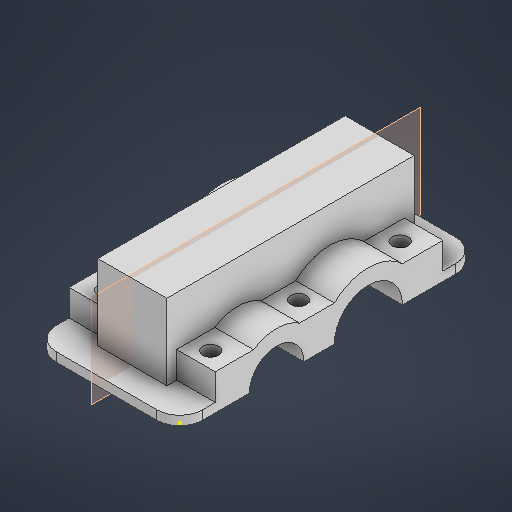
# Autodesk Inventor part: 箱盖
Saved by Autodesk Inventor 2026 (Build 300175000, 175)
## iProperties
Created: 2026-08-27
Part Number: 箱盖
Material: 常规
Document SubType Name: Modeling
Designer: 14170
Density: 1 g/cm^3
Appearance: 默认
Author: 14170
Autodesk Inventor part; units mm, degrees
ref_plane "YZ Plane" through (0, 0, 0) normal (1, 0, 0) x (0, 1, 0)
ref_plane "XZ Plane" through (0, 0, 0) normal (0, 1, 0) x (-1, 0, 0)
ref_plane "XY Plane" through (0, 0, 0) normal (0, 0, 1) x (1, 0, 0)
sketch "草图1" plane through (0, 0, 0) normal (0, 1, 0) x (-1, 0, 0)
  line L0 (0, -30) -> (0, -364.6)
  line L1 (30, -394.6) -> (163, -394.6)
  line L2 (193, -364.6) -> (193, -30)
  line L3 (163, 0) -> (30, 0)
  arc A0 (163, -394.6) -> (193, -364.6) centre (163, -364.6) ccw
  arc A1 (0, -364.6) -> (30, -394.6) centre (30, -364.6) ccw
  arc A2 (30, 0) -> (0, -30) centre (30, -30) ccw
  arc A3 (193, -30) -> (163, 0) centre (163, -30) ccw
  point P0 (0, 0)
  point P1 (0, -394.6)
  point P2 (193, -394.6)
  point P3 (193, 0)
  dimension "d0" = 394.6
  dimension "d1" = 193
  dimension "d46" = 30
  constraints: 8 end point, 8 point on circle, 8 point on line, 8 tangent, 4 centre point, 3 equal radius, 3 perpendicular, 1 vertical
  measures "d0" distance of point (0, 0) point (0, -394.6)
  measures "d1" distance of point (0, -394.6) point (193, -394.6)
  measures "d46" radius of A0
extrude "拉伸1" add sketch "草图1" along normal blind 12
sketch "草图2" plane through (0, 12, 0) normal (0, 1, 0) x (1, 0, 0)
  line L0 (-51, 34) -> (-51, 360.6)
  line L1 (-51, 360.6) -> (-142, 360.6)
  line L2 (-142, 360.6) -> (-142, 34)
  line L3 (-142, 34) -> (-51, 34)
  line L4 (0, 0) -> (0, 364.6) projected
  line L5 (-163, 0) -> (0, 0) projected
  point P0 (0, 394.6)
  point P1 (-193, 0)
  point P2 (-96.5, 34)
  dimension "d4" = 326.6
  dimension "d5" = 91
  dimension "d6" = 51
  dimension "d7" = 34
  constraints: 8 end point, 3 perpendicular, 1 midpoint, 1 vertical
  measures "d4" distance of L0.start L0.end
  measures "d5" distance of L0.end L1.end
  measures "d6" distance between parallel lines of L4 L0
  measures "d7" distance from line of L5 point (-96.5, 34)
extrude "拉伸2" add sketch "草图2" along normal blind 100
sketch "草图3" plane through (0, 12, 0) normal (0, 1, 0) x (1, 0, 0)
  line L0 (-193, 364.6) -> (-193, 30) projected
  line L1 (-193, 47) -> (0, 47)
  line L2 (0, 0) -> (0, 364.6) projected
  line L3 (0, 347.6) -> (-193, 347.6)
  line L4 (-193, 47) -> (-193, 347.6)
  line L5 (0, 347.6) -> (0, 47)
  point P0 (-193, 394.6)
  point P1 (-193, 0)
  point P2 (0, 394.6)
  constraints: 8 end point, 3 point on line, 2 collinear, 1 horizontal, 1 perpendicular
extrude "拉伸3" add sketch "草图3" along normal blind 35
ref_plane "工作平面1" through (-96.5, 12, -360.6) normal (1, 0, 0) x (0, 0, -1)
sketch "草图4" plane through (0, 0, 0) normal (1, 0, 0) x (0, 0, -1)
  line L0 (364.6, 0) -> (0, 0) projected
  arc A0 (294.2, 0) -> (204.2, 0) centre (249.2, 0) ccw
  arc A1 (314.2, 0) -> (184.2, 0) centre (249.2, 0) ccw
  arc A2 (163.95, 0) -> (91.95, 0) centre (127.95, 0) ccw
  arc A3 (183.95, 0) -> (71.95, 0) centre (127.95, 0) ccw
  line L1 (71.95, 0) -> (314.2, 0)
  point P0 (394.6, 0)
  dimension "d12" = 90
  dimension "d13" = 130
  dimension "d14" = 145.4
  dimension "d15" = 72
  dimension "d16" = 121.25
  dimension "d17" = 112
  constraints: 10 point on line, 8 point on circle, 4 centre point, 2 coincident, 2 end point
  measures "d12" diameter of A0
  measures "d13" diameter of A1
  measures "d14" distance of point (394.6, 0) A0.centre
  measures "d15" diameter of A2
  measures "d16" distance of A0.centre A2.centre
  measures "d17" diameter of A3
extrude "拉伸4" add sketch "草图4" against normal through all contours L0 A2 A3 | L0 A0 A1
extrude "拉伸5" add sketch "草图4" against normal blind 193
extrude "拉伸6" cut sketch "草图4" against normal blind 193 contours L0 A0 | L0 A2
sketch "草图5" plane through (0, 0, 0) normal (0, -1, 0) x (1, 0, 0)
  line L0 (-134, -352) -> (-59, -352)
  line L1 (-193, -91.95) -> (-193, -294.2) projected
  line L2 (-163, 0) -> (0, 0) projected
  line L3 (-134, -352) -> (-134, -42)
  line L4 (-51, -47) -> (0, -47) projected
  line L5 (-134, -42) -> (-59, -42)
  line L6 (-59, -42) -> (-59, -352)
  point P0 (-193, 0)
  dimension "d25" = 75
  dimension "d29" = 310
  dimension "d31" = 75
  dimension "d32" = 42
  dimension "d33" = 59
  constraints: 8 end point, 1 horizontal, 1 perpendicular, 1 vertical
  measures "d25" distance of L0.start L0.end
  measures "d29" distance of L0.start L3.end
  measures "d31" distance of L3.end L5.end
  measures "d32" distance between parallel lines of L2 L5
  measures "d33" distance between parallel lines of L1 L3
extrude "拉伸7" cut sketch "草图5" against normal blind 103
sketch "草图6" plane through (0, 47, 0) normal (0, 1, 0) x (1, 0, 0)
  circle A0 centre (-27, 67.95) radius 10.5
  circle A1 centre (-27, 184.1) radius 10.5
  circle A2 centre (-27, 318.2) radius 10.5
  line L0 (0, 294.2) -> (0, 204.2) projected
  line L1 (-51, 47) -> (-51, 97.5033) projected
  line L2 (-51, 158.3967) -> (-51, 204.3001) projected
  line L3 (-51, 294.0999) -> (-51, 347.6) projected
  line L4 (-142, 34) -> (-51, 34) projected
  line L5 (-96.5, 34) -> (-96.5, 360.6)
  line L6 (-51, 360.6) -> (-142, 360.6) projected
  circle A3 centre (-166, 67.95) radius 10.5
  circle A4 centre (-166, 184.1) radius 10.5
  circle A5 centre (-166, 318.2) radius 10.5
  point P0 (0, 0)
  point P1 (0, 249.2)
  point P2 (-51, 181.3484)
  dimension "d36" = 21
  dimension "d37" = 21
  dimension "d38" = 21
  dimension "d39" = 65.1
  dimension "d40" = 69
  dimension "d41" = 24
  dimension "d42" = 24
  dimension "d43" = 24
  constraints: 6 centre point, 4 midpoint, 3 symmetric about line, 2 end point, 3 other
  measures "d36" diameter of A0
  measures "d37" diameter of A1
  measures "d38" diameter of A2
  measures "d39" vertical distance of A1.centre point (0, 249.2)
  measures "d40" vertical distance of A2.centre point (0, 249.2)
  measures "d41" distance from line of L1 A0.centre
  measures "d42" horizontal distance of point (-51, 181.348) A1.centre
  measures "d43" distance from line of L3 A2.centre
extrude "拉伸8" cut sketch "草图6" against normal through all
sketch "草图7" plane through (0, 12, 0) normal (0, 1, 0) x (1, 0, 0)
  point P0 (0, 0)
